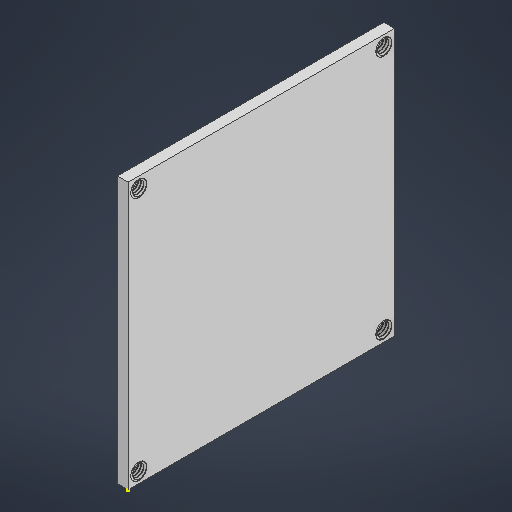
# Autodesk Inventor part: 22.10.2025-14
Saved by Autodesk Inventor 2026.1 (Build 301233020, 233B)
## iProperties
Created: 2026-01-04
Part Number: 22.10.2025-14
Material: Ogólny
Document SubType Name: Modeling
Designer: Nitro
Density: 1 g/cm^3
Appearance: Domyślna
Description: Pokrywa silnika
Author: Nitro
Autodesk Inventor part; units mm, degrees
ref_plane "YZ Plane" through (0, 0, 0) normal (1, 0, 0) x (0, 1, 0)
ref_plane "XZ Plane" through (0, 0, 0) normal (0, 1, 0) x (-1, 0, 0)
ref_plane "XY Plane" through (0, 0, 0) normal (0, 0, 1) x (1, 0, 0)
sketch "Szkic3" plane through (0, 0, 0) normal (1, 0, 0) x (0, 1, 0)
  line L0 (0, 0) -> (50, 0)
  line L1 (50, 0) -> (50, -50)
  line L2 (50, -50) -> (0, -50)
  line L3 (0, -50) -> (0, 0)
  point P0 (2, -2)
  point P1 (2, -48)
  point P2 (48, -48)
  point P3 (48, -2)
  dimension "d4" = 50
  dimension "d5" = 50
  dimension "d6" = 2
  dimension "d7" = 2
  dimension "d8" = 46
  dimension "d9" = 46
  dimension "d10" = 46
  dimension "d11" = 2
  dimension "d12" = 2
  dimension "d13" = 46
  constraints: 8 end point, 2 parallel, 1 horizontal, 1 perpendicular
  measures "d4" distance of L1.end L2.end
  measures "d5" distance of L0.end L1.end
  measures "d6" distance from line of L3 point (2, -2)
  measures "d7" distance from line of L0 point (2, -2)
  measures "d8" distance of point (2, -48) point (2, -2)
  measures "d9" distance of point (2, -2) point (48, -2)
  measures "d10" distance of point (48, -48) point (48, -2)
  measures "d11" distance from line of L3 point (2, -48)
  measures "d12" distance from line of L0 point (48, -2)
  measures "d13" distance of point (2, -48) point (48, -48)
extrude "Wyciągnięcie proste1" add sketch "Szkic3" along normal blind 2
sketch "Szkic4" plane through (2, 0, 0) normal (1, 0, 0) x (0, 0, -1)
  point P0 (0, 0)
sketch "Szkic5" plane through (0, 0, 0) normal (-1, 0, 0) x (0, 0, 1)
  line L0 (0, 50) -> (0, 0) projected
  line L1 (0, 0) -> (-50, 0) projected
  line L2 (-50, 50) -> (0, 50) projected
  line L3 (-50, 0) -> (-50, 50) projected
  point P0 (-2, 2)
  point P1 (-48, 2)
  point P2 (-48, 48)
  point P3 (-2, 48)
  dimension "d16" = 2
  dimension "d17" = 2
  dimension "d18" = 2
  dimension "d19" = 2
  dimension "d20" = 2
  dimension "d21" = 2
  dimension "d22" = 2
  dimension "d23" = 2
  measures "d16" distance from line of L0 point (-2, 2)
  measures "d17" distance from line of L1 point (-2, 2)
  measures "d18" distance from line of L0 point (-2, 48)
  measures "d19" distance from line of L2 point (-2, 48)
  measures "d20" distance from line of L2 point (-48, 48)
  measures "d21" distance from line of L3 point (-48, 48)
  measures "d22" distance from line of L3 point (-48, 2)
  measures "d23" distance from line of point (-48, 2) L1
hole "Otwór1" at (0, 2, -2) at (0, 2, -48) at (0, 48, -48) at (0, 48, -2) direction (1, 0, 0) diameter 3 depth 10
thread "Gwint1" size "M3x0.5" class "6H" standard "ANSI Metric M Profile" full length
thread "Gwint2" size "M3x0.5" class "6H" standard "ANSI Metric M Profile" full length
thread "Gwint3" size "M3x0.5" class "6H" standard "ANSI Metric M Profile" full length
thread "Gwint4" size "M3x0.5" class "6H" standard "ANSI Metric M Profile" full length
sketch "Szkic7" plane through (0, 2, -2) normal (0, 1, 0) x (0, 0, 1)
  line L0 (1.5, 0) -> (1.5, 2)
  line L1 (1.5, 2) -> (1.1293, 2)
  line L2 (1.1293, 2) -> (1.1293, 0)
  line L3 (1.1293, 0) -> (1.5, 0)
  line L4 (0, -1.0544) -> (0, 2.5091) projected
  constraints: 8 end point
revolve "Obrót1" add sketch "Szkic7" angle 360 about axis through (0, 2, -2) along (1, 0, 0) separate body
sketch "Szkic6" plane through (0, 2, -0.5) normal (0, -1, 0) x (1, 0, 0)
  line L0 (-0.2918, -0.0255) -> (-0.2501, -0.0255) construction
  line L1 (0.0416, -0.3456) -> (-0.0001, -0.4257) construction
  line L2 (-0.5001, -0.4257) -> (-0.5418, -0.3456) construction
  line L3 (-0.2084, -0.0255) -> (-0.2501, 0.0546) construction
  line L4 (-0.2501, 0.0546) -> (-0.2918, -0.0255) construction
  line L5 (-0.5001, -0.4257) -> (-0.4584, -0.3456) construction
  line L6 (-0.2084, -0.0255) -> (-0.0418, -0.3456)
  line L7 (-0.5418, -0.3456) -> (-0.4584, -0.3456) construction
  arc A0 (-0.5418, -0.3456) -> (-0.5001, -0.3709) centre (-0.5001, -0.3239) ccw construction
  line L8 (0.0416, -0.3456) -> (-0.0418, -0.3456) construction
  line L9 (-0.5001, -0.4257) -> (-0.5001, -0.3456) construction
  line L10 (-0.0001, -0.4257) -> (-0.0001, -0.3456) construction
  line L11 (-0.2501, 0.0546) -> (-0.2501, -0.0002) construction
  line L12 (-0.5001, -0.3709) -> (-0.0001, -0.3709)
  arc A1 (-0.5001, -0.3709) -> (-0.4584, -0.3456) centre (-0.5001, -0.3239) ccw
  line L13 (-0.0418, -0.3456) -> (-0.0001, -0.4257) construction
  line L14 (-0.4584, -0.3456) -> (-0.2918, -0.0255)
  line L15 (-0.0001, -0.0002) -> (-0.0001, 0.0177)
  line L16 (-0.0001, 0.0177) -> (-0.0001, -0.0002)
  line L17 (-0.0001, -0.0002) -> (0.0334, -0.0002)
  arc A2 (-0.0418, -0.3456) -> (-0.0001, -0.3709) centre (-0.0001, -0.3239) ccw
  arc A3 (-0.0001, -0.3709) -> (0.0416, -0.3456) centre (-0.0001, -0.3239) ccw construction
  arc A4 (-0.2501, -0.0002) -> (-0.2918, -0.0255) centre (-0.2501, -0.0471) ccw
  arc A5 (-0.2084, -0.0255) -> (-0.2501, -0.0002) centre (-0.2501, -0.0471) ccw
  line L18 (-0.2501, -0.0002) -> (-0.2501, -0.0255) construction
  line L19 (-0.2501, -0.0255) -> (-0.2084, -0.0255) construction
  dimension "d39" = 55
  dimension "d40" = 0.08
  dimension "d41" = 0.08
  dimension "Szkic6_ThreadOffset" = 0
  dimension "Szkic6_MajorRadius" = 0.3707
  dimension "d44" = 0.5
  dimension "Szkic6_MinorRadius" = 0
  constraints: 40 end point, 12 point on circle, 10 parallel, 8 tangent, 6 centre point, 6 collinear, 2 midpoint, 2 point on line, 1 horizontal, 1 perpendicular, 3 other
  measures "d39" angle of L6 L14
  measures "d40" distance of L3.end L0.end
  measures "d41" distance of L1.end L10.end
  measures "Szkic6_ThreadOffset" distance between parallel lines of L15 L10
  measures "Szkic6_MajorRadius" distance from line of L12 L15.start
  measures "d44" distance from line of L1.end L9
  measures "Szkic6_MinorRadius" distance edge to line of A5 L17
coil "Zwój1" sketch "Szkic6" operation cut axis through (0, 2, -2) along (1, 0, 0) pitch 0.5005 turns 5.994006 hand right bodies 2
sketch "Szkic9" plane through (0, 48, -2) normal (0, 1, 0) x (0, 0, 1)
  line L0 (1.5, 0) -> (1.5, 2)
  line L1 (1.5, 2) -> (1.1293, 2)
  line L2 (1.1293, 2) -> (1.1293, 0)
  line L3 (1.1293, 0) -> (1.5, 0)
  line L4 (0, -1.0877) -> (0, 2.7091) projected
  constraints: 8 end point
revolve "Obrót2" add sketch "Szkic9" angle 360 about axis through (0, 48, -2) along (1, 0, 0) separate body
sketch "Szkic8" plane through (0, 48, -0.5) normal (0, -1, 0) x (1, 0, 0)
  line L0 (-0.2918, -0.0255) -> (-0.2501, -0.0255) construction
  line L1 (0.0416, -0.3456) -> (-0.0001, -0.4257) construction
  line L2 (-0.5001, -0.4257) -> (-0.5418, -0.3456) construction
  line L3 (-0.2084, -0.0255) -> (-0.2501, 0.0546) construction
  line L4 (-0.2501, 0.0546) -> (-0.2918, -0.0255) construction
  line L5 (-0.5001, -0.4257) -> (-0.4584, -0.3456) construction
  line L6 (-0.2084, -0.0255) -> (-0.0418, -0.3456)
  line L7 (-0.5418, -0.3456) -> (-0.4584, -0.3456) construction
  arc A0 (-0.5418, -0.3456) -> (-0.5001, -0.3709) centre (-0.5001, -0.3239) ccw construction
  line L8 (0.0416, -0.3456) -> (-0.0418, -0.3456) construction
  line L9 (-0.5001, -0.4257) -> (-0.5001, -0.3456) construction
  line L10 (-0.0001, -0.4257) -> (-0.0001, -0.3456) construction
  line L11 (-0.2501, 0.0546) -> (-0.2501, -0.0002) construction
  line L12 (-0.5001, -0.3709) -> (-0.0001, -0.3709)
  arc A1 (-0.5001, -0.3709) -> (-0.4584, -0.3456) centre (-0.5001, -0.3239) ccw
  line L13 (-0.0418, -0.3456) -> (-0.0001, -0.4257) construction
  line L14 (-0.4584, -0.3456) -> (-0.2918, -0.0255)
  line L15 (-0.0001, -0.0002) -> (-0.0001, 0.0177)
  line L16 (-0.0001, 0.0177) -> (-0.0001, -0.0002)
  line L17 (-0.0001, -0.0002) -> (0.0334, -0.0002)
  arc A2 (-0.0418, -0.3456) -> (-0.0001, -0.3709) centre (-0.0001, -0.3239) ccw
  arc A3 (-0.0001, -0.3709) -> (0.0416, -0.3456) centre (-0.0001, -0.3239) ccw construction
  arc A4 (-0.2501, -0.0002) -> (-0.2918, -0.0255) centre (-0.2501, -0.0471) ccw
  arc A5 (-0.2084, -0.0255) -> (-0.2501, -0.0002) centre (-0.2501, -0.0471) ccw
  line L18 (-0.2501, -0.0002) -> (-0.2501, -0.0255) construction
  line L19 (-0.2501, -0.0255) -> (-0.2084, -0.0255) construction
  dimension "d57" = 55
  dimension "d58" = 0.08
  dimension "d59" = 0.08
  dimension "Szkic8_ThreadOffset" = 0
  dimension "Szkic8_MajorRadius" = 0.3707
  dimension "d62" = 0.5
  dimension "Szkic8_MinorRadius" = 0
  constraints: 40 end point, 12 point on circle, 10 parallel, 8 tangent, 6 centre point, 6 collinear, 2 midpoint, 2 point on line, 1 horizontal, 1 perpendicular, 3 other
  measures "d57" angle of L6 L14
  measures "d58" distance of L3.end L0.end
  measures "d59" distance of L1.end L10.end
  measures "Szkic8_ThreadOffset" distance between parallel lines of L15 L10
  measures "Szkic8_MajorRadius" distance from line of L12 L15.start
  measures "d62" distance from line of L1.end L9
  measures "Szkic8_MinorRadius" distance edge to line of A5 L17
coil "Zwój2" sketch "Szkic8" operation cut axis through (0, 48, -2) along (1, 0, 0) pitch 0.5005 turns 5.994006 hand right bodies 3
sketch "Szkic11" plane through (0, 48, -48) normal (0, 1, 0) x (0, 0, 1)
  line L0 (1.5, 0) -> (1.5, 2)
  line L1 (1.5, 2) -> (1.1293, 2)
  line L2 (1.1293, 2) -> (1.1293, 0)
  line L3 (1.1293, 0) -> (1.5, 0)
  line L4 (0, -1.0877) -> (0, 2.7091) projected
  constraints: 8 end point
revolve "Obrót3" add sketch "Szkic11" angle 360 about axis through (0, 48, -48) along (1, 0, 0) separate body
sketch "Szkic10" plane through (0, 48, -46.5) normal (0, -1, 0) x (1, 0, 0)
  line L0 (-0.2918, -0.0255) -> (-0.2501, -0.0255) construction
  line L1 (0.0416, -0.3456) -> (-0.0001, -0.4257) construction
  line L2 (-0.5001, -0.4257) -> (-0.5418, -0.3456) construction
  line L3 (-0.2084, -0.0255) -> (-0.2501, 0.0546) construction
  line L4 (-0.2501, 0.0546) -> (-0.2918, -0.0255) construction
  line L5 (-0.5001, -0.4257) -> (-0.4584, -0.3456) construction
  line L6 (-0.2084, -0.0255) -> (-0.0418, -0.3456)
  line L7 (-0.5418, -0.3456) -> (-0.4584, -0.3456) construction
  arc A0 (-0.5418, -0.3456) -> (-0.5001, -0.3709) centre (-0.5001, -0.3239) ccw construction
  line L8 (0.0416, -0.3456) -> (-0.0418, -0.3456) construction
  line L9 (-0.5001, -0.4257) -> (-0.5001, -0.3456) construction
  line L10 (-0.0001, -0.4257) -> (-0.0001, -0.3456) construction
  line L11 (-0.2501, 0.0546) -> (-0.2501, -0.0002) construction
  line L12 (-0.5001, -0.3709) -> (-0.0001, -0.3709)
  arc A1 (-0.5001, -0.3709) -> (-0.4584, -0.3456) centre (-0.5001, -0.3239) ccw
  line L13 (-0.0418, -0.3456) -> (-0.0001, -0.4257) construction
  line L14 (-0.4584, -0.3456) -> (-0.2918, -0.0255)
  line L15 (-0.0001, -0.0002) -> (-0.0001, 0.0177)
  line L16 (-0.0001, 0.0177) -> (-0.0001, -0.0002)
  line L17 (-0.0001, -0.0002) -> (0.0334, -0.0002)
  arc A2 (-0.0418, -0.3456) -> (-0.0001, -0.3709) centre (-0.0001, -0.3239) ccw
  arc A3 (-0.0001, -0.3709) -> (0.0416, -0.3456) centre (-0.0001, -0.3239) ccw construction
  arc A4 (-0.2501, -0.0002) -> (-0.2918, -0.0255) centre (-0.2501, -0.0471) ccw
  arc A5 (-0.2084, -0.0255) -> (-0.2501, -0.0002) centre (-0.2501, -0.0471) ccw
  line L18 (-0.2501, -0.0002) -> (-0.2501, -0.0255) construction
  line L19 (-0.2501, -0.0255) -> (-0.2084, -0.0255) construction
  dimension "d75" = 55
  dimension "d76" = 0.08
  dimension "d77" = 0.08
  dimension "Szkic10_ThreadOffset" = 0
  dimension "Szkic10_MajorRadius" = 0.3707
  dimension "d80" = 0.5
  dimension "Szkic10_MinorRadius" = 0
  constraints: 40 end point, 12 point on circle, 10 parallel, 8 tangent, 6 centre point, 6 collinear, 2 midpoint, 2 point on line, 1 horizontal, 1 perpendicular, 3 other
  measures "d75" angle of L6 L14
  measures "d76" distance of L3.end L0.end
  measures "d77" distance of L1.end L10.end
  measures "Szkic10_ThreadOffset" distance between parallel lines of L15 L10
  measures "Szkic10_MajorRadius" distance from line of L12 L15.start
  measures "d80" distance from line of L1.end L9
  measures "Szkic10_MinorRadius" distance edge to line of A5 L17
coil "Zwój3" sketch "Szkic10" operation cut axis through (0, 48, -48) along (1, 0, 0) pitch 0.5005 turns 5.994006 hand right bodies 4
sketch "Szkic13" plane through (0, 2, -48) normal (0, 1, 0) x (0, 0, 1)
  line L0 (1.5, 0) -> (1.5, 2)
  line L1 (1.5, 2) -> (1.1293, 2)
  line L2 (1.1293, 2) -> (1.1293, 0)
  line L3 (1.1293, 0) -> (1.5, 0)
  line L4 (0, -1.0877) -> (0, 2.7091) projected
  constraints: 8 end point
revolve "Obrót4" add sketch "Szkic13" angle 360 about axis through (0, 2, -48) along (1, 0, 0) separate body
sketch "Szkic12" plane through (0, 2, -46.5) normal (0, -1, 0) x (1, 0, 0)
  line L0 (-0.2918, -0.0255) -> (-0.2501, -0.0255) construction
  line L1 (0.0416, -0.3456) -> (-0.0001, -0.4257) construction
  line L2 (-0.5001, -0.4257) -> (-0.5418, -0.3456) construction
  line L3 (-0.2084, -0.0255) -> (-0.2501, 0.0546) construction
  line L4 (-0.2501, 0.0546) -> (-0.2918, -0.0255) construction
  line L5 (-0.5001, -0.4257) -> (-0.4584, -0.3456) construction
  line L6 (-0.2084, -0.0255) -> (-0.0418, -0.3456)
  line L7 (-0.5418, -0.3456) -> (-0.4584, -0.3456) construction
  arc A0 (-0.5418, -0.3456) -> (-0.5001, -0.3709) centre (-0.5001, -0.3239) ccw construction
  line L8 (0.0416, -0.3456) -> (-0.0418, -0.3456) construction
  line L9 (-0.5001, -0.4257) -> (-0.5001, -0.3456) construction
  line L10 (-0.0001, -0.4257) -> (-0.0001, -0.3456) construction
  line L11 (-0.2501, 0.0546) -> (-0.2501, -0.0002) construction
  line L12 (-0.5001, -0.3709) -> (-0.0001, -0.3709)
  arc A1 (-0.5001, -0.3709) -> (-0.4584, -0.3456) centre (-0.5001, -0.3239) ccw
  line L13 (-0.0418, -0.3456) -> (-0.0001, -0.4257) construction
  line L14 (-0.4584, -0.3456) -> (-0.2918, -0.0255)
  line L15 (-0.0001, -0.0002) -> (-0.0001, 0.0177)
  line L16 (-0.0001, 0.0177) -> (-0.0001, -0.0002)
  line L17 (-0.0001, -0.0002) -> (0.0334, -0.0002)
  arc A2 (-0.0418, -0.3456) -> (-0.0001, -0.3709) centre (-0.0001, -0.3239) ccw
  arc A3 (-0.0001, -0.3709) -> (0.0416, -0.3456) centre (-0.0001, -0.3239) ccw construction
  arc A4 (-0.2501, -0.0002) -> (-0.2918, -0.0255) centre (-0.2501, -0.0471) ccw
  arc A5 (-0.2084, -0.0255) -> (-0.2501, -0.0002) centre (-0.2501, -0.0471) ccw
  line L18 (-0.2501, -0.0002) -> (-0.2501, -0.0255) construction
  line L19 (-0.2501, -0.0255) -> (-0.2084, -0.0255) construction
  dimension "d93" = 55
  dimension "d94" = 0.08
  dimension "d95" = 0.08
  dimension "Szkic12_ThreadOffset" = 0
  dimension "Szkic12_MajorRadius" = 0.3707
  dimension "d98" = 0.5
  dimension "Szkic12_MinorRadius" = 0
  constraints: 40 end point, 12 point on circle, 10 parallel, 8 tangent, 6 centre point, 6 collinear, 2 midpoint, 2 point on line, 1 horizontal, 1 perpendicular, 3 other
  measures "d93" angle of L6 L14
  measures "d94" distance of L3.end L0.end
  measures "d95" distance of L1.end L10.end
  measures "Szkic12_ThreadOffset" distance between parallel lines of L15 L10
  measures "Szkic12_MajorRadius" distance from line of L12 L15.start
  measures "d98" distance from line of L1.end L9
  measures "Szkic12_MinorRadius" distance edge to line of A5 L17
coil "Zwój4" sketch "Szkic12" operation cut axis through (0, 2, -48) along (1, 0, 0) pitch 0.5005 turns 5.994006 hand right bodies 5
equation "\"d39\" = d46"
equation "\"d40\" = 0.160083 * Szkic6_Pitch"
equation "\"d41\" = 0.160083 * Szkic6_Pitch"
equation "\"d44\" = Szkic6_Pitch"
equation "\"d57\" = d64"
equation "\"d58\" = 0.160083 * Szkic8_Pitch"
equation "\"d59\" = 0.160083 * Szkic8_Pitch"
equation "\"d62\" = Szkic8_Pitch"
equation "\"d75\" = d82"
equation "\"d76\" = 0.160083 * Szkic10_Pitch"
equation "\"d77\" = 0.160083 * Szkic10_Pitch"
equation "\"d80\" = Szkic10_Pitch"
equation "\"d93\" = d100"
equation "\"d94\" = 0.160083 * Szkic12_Pitch"
equation "\"d95\" = 0.160083 * Szkic12_Pitch"
equation "\"d98\" = Szkic12_Pitch"
equation "\"d46\" = 55deg"
equation "\"Szkic6_Pitch\" = 0.5"
equation "\"d64\" = 55deg"
equation "\"Szkic8_Pitch\" = 0.5"
equation "\"d82\" = 55deg"
equation "\"Szkic10_Pitch\" = 0.5"
equation "\"d100\" = 55deg"
equation "\"Szkic12_Pitch\" = 0.5"
